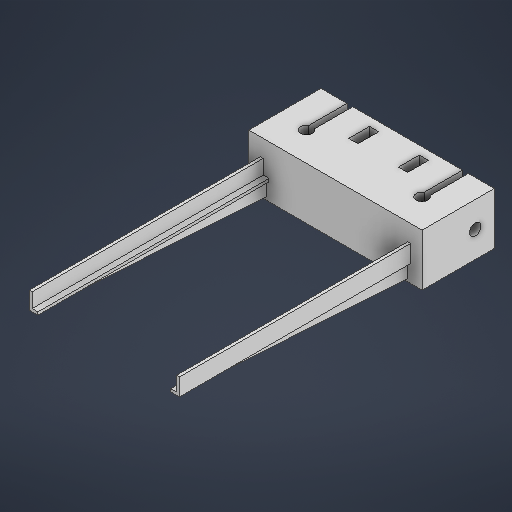
# Autodesk Inventor part: Prowadnica szynowa do kamery
Saved by Autodesk Inventor 2026.4 (Build 304435000, 435)
## iProperties
Created: 2026-10-04
Part Number: Prowadnica szynowa do kamery
Material: Generic
Document SubType Name: Modeling
Designer: Matol
Density: 1 g/cm^3
Appearance: Default
Author: Matol
Autodesk Inventor part; units mm, degrees
ref_plane "YZ Plane" through (0, 0, 0) normal (1, 0, 0) x (0, 1, 0)
ref_plane "XZ Plane" through (0, 0, 0) normal (0, 1, 0) x (-1, 0, 0)
ref_plane "XY Plane" through (0, 0, 0) normal (0, 0, 1) x (1, 0, 0)
sketch "Sketch1" plane through (0, 0, 0) normal (0, 1, 0) x (-1, 0, 0)
  line L0 (-30, -12.5) -> (-30, 12.5)
  arc A0 (-19, 0.7104) -> (-21, 0.7104) centre (-20, 2.5) ccw
  line L1 (-30, -12.5) -> (-21, -12.5)
  line L2 (-21, -12.5) -> (-21, 0.7104)
  line L3 (-19, -12.5) -> (-19, 0.7104)
  line L4 (-30, 12.5) -> (0, 12.5)
  line L5 (0, 12.5) -> (0, -12.5)
  line L6 (0, -12.5) -> (-19, -12.5)
  point P0 (0, 0)
  point P1 (-30, 0)
  point P2 (-21, -5.8948)
  point P3 (-19, -5.8948)
  dimension "d8" = 2.05
  dimension "d11" = 30
  dimension "d13" = 25
  dimension "d25" = 10
  dimension "d27" = 2
  dimension "d28" = 20
  constraints: 14 end point, 3 horizontal alignment, 3 midpoint, 3 perpendicular, 2 horizontal, 2 point on circle, 2 vertical, 1 centre point, 1 vertical alignment
  measures "d8" radius of A0
  measures "d11" distance of L0.end L4.end
  measures "d13" distance of L0.start L0.end
  measures "d25" distance from line of L4 A0.centre
  measures "d27" distance between parallel lines of L2 L3
  measures "d28" distance from line of L5 A0.centre
extrude "Extrusion1" add sketch "Sketch1" along normal mid plane 18
sketch "Sketch2" plane through (30, -9, -12.5) normal (1, 0, 0) x (0, 0, -1)
  line L0 (-13.2104, 18) -> (-13.2104, 0) projected
  line L1 (0, 0) -> (0, 18) projected
  line L2 (-6.6052, 9) -> (-13.2104, 9) construction
  line L3 (-6.6052, 9) -> (0, 9) construction
  point P0 (-12.5, 9)
  constraints: 4 end point, 2 midpoint, 1 coincident, 1 collinear, 1 horizontal alignment, 1 perpendicular
hole "Hole1" at (30, 0, -5.8948) direction (-1, 0, 0) diameter 4 depth 26 tip angle 118
sketch "Sketch3" plane through (0, 9, 0) normal (0, 1, 0) x (1, 0, 0)
  line L0 (4, 7.8948) -> (19, 7.8948) projected
  line L1 (4, 3.8948) -> (19, 3.8948) projected
  line L2 (4, 3.8948) -> (4, 7.8948) projected
  line L3 (7, 9.4948) -> (10.2, 9.4948)
  line L4 (10.2, 9.4948) -> (10.2, 2.2948)
  line L5 (10.2, 2.2948) -> (7, 2.2948)
  line L6 (7, 2.2948) -> (7, 9.4948)
  point P0 (0, 0)
  point P1 (7, 5.8948)
  point P2 (4, 5.8948)
  dimension "d22" = 3.2
  dimension "d23" = 7.2
  dimension "d26" = 3
  constraints: 8 end point, 2 midpoint, 2 parallel, 1 horizontal, 1 horizontal alignment, 1 perpendicular
  measures "d22" distance of L4.end L5.end
  measures "d23" distance of L3.end L4.end
  measures "d26" distance of point (7, 5.895) point (4, 5.895)
extrude "Extrusion2" cut sketch "Sketch3" against normal blind 13 contours L6 L3 L4 L0 | L0 L4 L1 L6 | L1 L4 L5 L6
mirror "Mirror1" about plane through (0, 0, -12.5) normal (-1, 0, 0)
sketch "Sketch4" plane through (30, -9, 12.5) normal (0, 0, 1) x (1, 0, 0)
  line L0 (-55, 7) -> (-55, 12)
  line L1 (-55, 12) -> (-56, 12)
  line L2 (-56, 12) -> (-56, 6)
  line L3 (0, 0) -> (0, 18) projected
  line L4 (-55, 7) -> (-53, 7)
  line L5 (-53, 7) -> (-53, 6)
  line L6 (-53, 6) -> (-56, 6)
  line L7 (-60, 0) -> (-60, 18) projected
  line L8 (-30, 7.2399) -> (-30, 3) construction
  point P0 (-30, 9)
  point P1 (0, 9)
  point P2 (-56, 9)
  point P3 (-60, 9)
  dimension "d33" = 5
  dimension "d34" = 1
  dimension "d36" = 2
  dimension "d37" = 1
  dimension "d38" = 25
  constraints: 14 end point, 4 vertical, 3 midpoint, 3 perpendicular, 1 horizontal, 1 horizontal alignment, 2 other
  measures "d33" distance of L0.start L0.end
  measures "d34" distance of L0.end L1.end
  measures "d36" distance of L0.start L4.end
  measures "d37" distance of L4.end L5.end
  measures "d38" distance from line of point (-30, 9) L0
extrude "Extrusion3" add sketch "Sketch4" along normal blind 80
ref_plane "Work Plane1" through (-24.5, -3, 12.5) normal (1, 0, 0) x (0, 0, -1)
sketch "Sketch7" plane through (-24.5, -3, 12.5) normal (1, 0, 0) x (0, 0, -1)
  line L0 (0, -5) -> (-78, 0)
  line L1 (-80, 0) -> (-80, 1) projected
  line L2 (25, -6) -> (0, -6) projected
  line L3 (0, -6) -> (0, 12) projected
  line L4 (0, 0) -> (-80, 0) projected
  point P0 (12.5, 3)
  dimension "d55" = 2
  dimension "d56" = 1
  constraints: 2 end point, 2 point on line
  measures "d55" distance from line of L1 L0.end
  measures "d56" distance from line of L2 L0.start
extrude "Rib3" add sketch "Sketch7" along normal mid plane 1 rib yes fills toward (-38.9968, -2.4501) open curves L0
mirror "Mirror2" about plane through (0, 0, 0) normal (1, 0, 0) of "Extrusion3", "Rib3"
body "Solid1"
